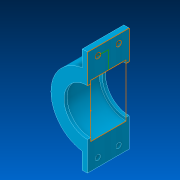
# Autodesk Inventor part: Bilge Pump Holder
Saved by Autodesk Inventor 2019 (Build 230136000, 136)
## iProperties
Created: 2018-10-23
Part Number: Bilge Pump Holder
Material: Generic
Document SubType Name: Modeling
Designer: -----
Density: 1 g/cm^3
Appearance: Sky Blue Medium
Mass: 43.4068 g
Surface Area: 140.518 cm^2
Volume: 43.4068 cm^3
Author: -----
Autodesk Inventor part; units mm, degrees
ref_plane "YZ Plane" through (0, 0, 0) normal (1, 0, 0) x (0, 1, 0)
ref_plane "XZ Plane" through (0, 0, 0) normal (0, 1, 0) x (-1, 0, 0)
ref_plane "XY Plane" through (0, 0, 0) normal (0, 0, 1) x (1, 0, 0)
sketch "Sketch1" plane through (0, 0, 0) normal (0, 1, 0) x (-1, 0, 0)
  line L0 (-0.1069, 50.4998) -> (-0.1069, 25.4998)
  arc A0 (-0.1069, -25.4998) -> (-0.1069, 25.4998) centre (0, 0) ccw
  line L1 (-0.1069, -25.4998) -> (-0.1069, -50.4998)
  line L2 (-0.1069, 50.4998) -> (4.8931, 50.4998)
  line L3 (4.8931, 50.4998) -> (4.8931, 34.6563)
  line L4 (4.8931, -34.6563) -> (4.8931, -50.4998)
  line L5 (4.8931, -50.4998) -> (-0.1069, -50.4998)
  arc A1 (4.8931, -34.6563) -> (4.8931, 34.6563) centre (0, 0) ccw
  circle A2 centre (0, 0) radius 25.5 projected
  dimension "d0" = 51
  dimension "d2" = 25
  dimension "d3" = 5
  dimension "d4" = 25
  dimension "d12" = 35
  constraints: 12 end point, 4 point on circle, 3 point on line, 2 centre point, 2 coincident, 2 vertical, 1 collinear, 1 horizontal, 1 perpendicular
  measures "d0" diameter of A0
  measures "d2" distance of L0.start L0.end
  measures "d3" distance of L0.start L2.end
  measures "d4" distance of L1.start L1.end
  measures "d12" radius of A1
extrude "Extrusion1" add sketch "Sketch1" along normal blind 34 contours L2 L3 A1 L4 L5 L1 A0 L0
sketch "Sketch2" plane through (0, 34, 0) normal (0, 1, 0) x (1, 0, 0)
  line L0 (0.1069, -50.4998) -> (0.1069, -25.4998) projected
  arc A0 (0.1069, 25.4998) -> (0.1069, -25.4998) centre (0, 0) ccw projected
  line L1 (0.1069, 25.4998) -> (0.1069, 50.4998) projected
  line L2 (0.1069, 50.4998) -> (-4.8931, 50.4998) projected
  line L3 (-4.8931, 50.4998) -> (-4.8931, 34.6563) projected
  arc A1 (-4.8931, 34.6563) -> (-4.8931, -34.6563) centre (0, 0) ccw projected
  line L4 (-4.8931, -34.6563) -> (-4.8931, -50.4998) projected
  line L5 (-4.8931, -50.4998) -> (0.1069, -50.4998) projected
  circle A2 centre (0, 0) radius 22.5
  line L6 (0.1069, -22.4997) -> (0.1069, -25.4998)
  line L7 (0.1069, 22.4997) -> (0.1069, 25.4998)
  dimension "d7" = 45
  constraints: 4 end point, 2 point on circle, 1 centre point, 1 coincident, 1 collinear, 1 point on line, 1 vertical
  measures "d7" diameter of A2
extrude "Extrusion2" add sketch "Sketch2" along normal blind 3 contours L5 L4 A1 L3 L2 L1 A0 L0 | A0 L7 A2 L6
sketch "Sketch8" plane through (0, 0, 0) normal (0, -1, 0) x (1, 0, 0)
  line L0 (0.1069, 50.4998) -> (0.1069, 25.4998) projected
  line L1 (-4.8931, 50.4998) -> (0.1069, 50.4998) projected
  line L2 (-4.8931, 34.6563) -> (-4.8931, 50.4998) projected
  arc A0 (-4.8931, 34.6563) -> (-4.8931, -34.6563) centre (0, 0) ccw projected
  line L3 (-4.8931, -50.4998) -> (-4.8931, -34.6563) projected
  line L4 (0.1069, -50.4998) -> (-4.8931, -50.4998) projected
  line L5 (0.1069, -25.4998) -> (0.1069, -50.4998) projected
  arc A1 (0.1069, 25.4998) -> (0.1069, -25.4998) centre (0, 0) ccw projected
  arc A2 (0.1069, 22.4997) -> (0.1069, -22.4997) centre (0, 0) ccw projected
  line L6 (0.1069, -22.4997) -> (0.1069, -25.4998) projected
  line L7 (0.1069, 25.4998) -> (0.1069, 22.4997) projected
extrude "Extrusion7" add sketch "Sketch8" along normal blind 3
sketch "Sketch9" plane through (-4.8931, 37, 34.6563) normal (-1, 0, 0) x (0, 0, 1)
  circle A0 centre (7.8435, -10) radius 2.5
  line L0 (0, 0) -> (15.8435, 0) projected
  line L1 (15.8435, -40) -> (15.8435, 0) projected
  line L2 (-34.6563, 54.1442) -> (-34.6563, -76.272)
  line L3 (-113.0163, -20) -> (111.5791, -20)
  circle A1 centre (-77.1561, -10) radius 2.5
  line L4 (43.7038, -20) -> (-180.8916, -20)
  circle A2 centre (7.8435, -30) radius 2.5
  circle A3 centre (-77.1561, -30) radius 2.5
  point P0 (-34.6563, -37)
  dimension "d49" = 5
  dimension "d53" = 10
  dimension "d54" = 8
  dimension "d55" = 20
  dimension "d56" = 50.4998
  constraints: 6 end point, 5 symmetric about line, 4 centre point, 1 horizontal, 1 vertical, 3 other
  measures "d49" diameter of A0
  measures "d53" distance from line of L0 A0.centre
  measures "d54" distance from line of L1 A0.centre
  measures "d55" distance between parallel lines of L3 L0
  measures "d56" distance between parallel lines of L2 L1
hole "Hole2" at (-4.8931, 27, -42.4998) at (-4.8931, 7, -42.4998) at (-4.8931, 27, 42.4998) at (-4.8931, 7, 42.4998) direction (1, 0, 0) diameter 5 end through all
sketch "Sketch11" plane through (0.1069, 34, 25.4998) normal (1, 0, 0) x (0, 0, -1)
  circle A0 centre (-17, -7) radius 2.5 projected
  circle A1 centre (-17, -27) radius 2.5 projected
  line L0 (0, -34) -> (0, 0) projected
  line L1 (0, 0) -> (3, 0) projected
  line L2 (3, 0) -> (3, 3) projected
  line L3 (-25, 3) -> (3, 3) projected
  line L4 (-25, 3) -> (-25, -37) projected
  line L5 (3, -37) -> (-25, -37) projected
  line L6 (3, -34) -> (3, -37) projected
  line L7 (3, -34) -> (0, -34) projected
  line L8 (0, -34) -> (50.9996, -34) projected
  line L9 (50.9996, -34) -> (50.9996, 0) projected
  line L10 (0, 0) -> (50.9996, 0) projected
  line L11 (0, -34) -> (0, 0) projected
  line L12 (0, -34) -> (0, 0) projected
  line L13 (0, -17) -> (-17, -17)
  circle A2 centre (-17, -27) radius 2.5 projected
  line L14 (-17, -17) -> (-17, -27)
  point P0 (25.4998, -34)
  constraints: 4 end point, 1 horizontal, 1 midpoint, 1 perpendicular
body "Solid1"
